Autodesk Fusion 360 part; units mm, degrees
(part 2 of 3)
sketch "Tip bolt 102 -10 sketch" plane through (0, 0, -0.05) normal (0, 0, 1) x (1, 0, 0) in component "01C Wing tip - load adapter"
  circle A0 centre (102, -10) radius 1.7
  dimension "d328" = 3.4
  measures "d328" diameter of A0
extrude "Tip bolt 102 -10" cut sketch "Tip bolt 102 -10 sketch" along normal blind 9.1 bodies 3 in component "01C Wing tip - load adapter"
ref_plane "WorkPlane15" through (0, 0, -0.05) normal (0, 0, 1) x (1, 0, 0) in component "01C Wing tip - load adapter"
sketch "Tip bolt 102 10 sketch" plane through (0, 0, -0.05) normal (0, 0, 1) x (1, 0, 0) in component "01C Wing tip - load adapter"
  circle A0 centre (102, 10) radius 1.7
  dimension "d333" = 3.4
  measures "d333" diameter of A0
extrude "Tip bolt 102 10" cut sketch "Tip bolt 102 10 sketch" along normal blind 9.1 bodies 3 in component "01C Wing tip - load adapter"
ref_plane "WorkPlane16" through (0, 0, -0.05) normal (0, 0, 1) x (1, 0, 0) in component "01C Wing tip - load adapter"
sketch "Tip bolt 110 -10 sketch" plane through (0, 0, -0.05) normal (0, 0, 1) x (1, 0, 0) in component "01C Wing tip - load adapter"
  circle A0 centre (110, -10) radius 1.7
  dimension "d338" = 3.4
  measures "d338" diameter of A0
extrude "Tip bolt 110 -10" cut sketch "Tip bolt 110 -10 sketch" along normal blind 9.1 bodies 3 in component "01C Wing tip - load adapter"
ref_plane "WorkPlane17" through (0, 0, -0.05) normal (0, 0, 1) x (1, 0, 0) in component "01C Wing tip - load adapter"
sketch "Tip bolt 110 10 sketch" plane through (0, 0, -0.05) normal (0, 0, 1) x (1, 0, 0) in component "01C Wing tip - load adapter"
  circle A0 centre (110, 10) radius 1.7
  dimension "d343" = 3.4
  measures "d343" diameter of A0
extrude "Tip bolt 110 10" cut sketch "Tip bolt 110 10 sketch" along normal blind 9.1 bodies 3 in component "01C Wing tip - load adapter"
ref_plane "WorkPlane18" through (-0.05, 0, 0) normal (1, 0, 0) x (0, 1, 0) in component "01C Wing tip - load adapter"
sketch "front diamond bamboo passage sketch (3)" plane through (-0.05, 0, 0) normal (1, 0, 0) x (0, 0, -1) in component "01C Wing tip - load adapter"
  line L0 (-4.5, -21.182) -> (-1.318, -18)
  line L1 (-1.318, -18) -> (-4.5, -14.818)
  line L2 (-4.5, -14.818) -> (-7.682, -18)
  line L3 (-7.682, -18) -> (-4.5, -21.182)
  line L4 (-4.5, -21.182) -> (-4.5, -14.818) construction
  line L5 (-1.318, -18) -> (-7.682, -18) construction
  point P0 (-4.5, -18)
  dimension "d348" = 6.364
  constraint vertical L4
  constraint horizontal L5
  constraint midpoint L4 P0
  constraint midpoint L5 P0
  constraint equal L4 L5
  measures "d348" distance of L0.end L2.end
extrude "front diamond bamboo passage''" cut sketch "front diamond bamboo passage sketch (3)" along normal blind 112.05 bodies 3 in component "01C Wing tip - load adapter"
ref_plane "WorkPlane19" through (-0.05, 0, 0) normal (1, 0, 0) x (0, 1, 0) in component "01C Wing tip - load adapter"
sketch "rear diamond bamboo passage sketch (3)" plane through (-0.05, 0, 0) normal (1, 0, 0) x (0, 0, -1) in component "01C Wing tip - load adapter"
  line L0 (-4.5, 14.818) -> (-1.318, 18)
  line L1 (-1.318, 18) -> (-4.5, 21.182)
  line L2 (-4.5, 21.182) -> (-7.682, 18)
  line L3 (-7.682, 18) -> (-4.5, 14.818)
  line L4 (-4.5, 14.818) -> (-4.5, 21.182) construction
  line L5 (-1.318, 18) -> (-7.682, 18) construction
  point P0 (-4.5, 18)
  dimension "d353" = 6.364
  constraint vertical L4
  constraint horizontal L5
  constraint midpoint L4 P0
  constraint midpoint L5 P0
  constraint equal L4 L5
  measures "d353" distance of L0.end L2.end
extrude "rear diamond bamboo passage''" cut sketch "rear diamond bamboo passage sketch (3)" along normal blind 112.05 bodies 3 in component "01C Wing tip - load adapter"
sketch "Flat joint plate sketch" plane through (0, 0, 0) normal (0, 0, 1) x (1, 0, 0) in component "07 Joint sandwich plate - print FOUR"
  line L0 (0, -10) -> (24.2, -10)
  line L1 (24.2, -10) -> (24.2, 10)
  line L2 (24.2, 10) -> (0, 10)
  line L3 (0, 10) -> (0, -10)
extrude "Flat joint plate" add sketch "Flat joint plate sketch" along normal blind 2 separate body makes body 4 in component "07 Joint sandwich plate - print FOUR"
ref_plane "WorkPlane1" through (0, 0, -0.05) normal (0, 0, 1) x (1, 0, 0) in component "07 Joint sandwich plate - print FOUR"
sketch "Seam bolt 6 sketch" plane through (0, 0, -0.05) normal (0, 0, 1) x (1, 0, 0) in component "07 Joint sandwich plate - print FOUR"
  circle A0 centre (6, 0) radius 1.7
  dimension "d360" = 3.4
  measures "d360" diameter of A0
extrude "Seam bolt 6" cut sketch "Seam bolt 6 sketch" along normal blind 2.1 bodies 4 in component "07 Joint sandwich plate - print FOUR"
ref_plane "WorkPlane2" through (0, 0, -0.05) normal (0, 0, 1) x (1, 0, 0) in component "07 Joint sandwich plate - print FOUR"
sketch "Seam bolt 18.2 sketch" plane through (0, 0, -0.05) normal (0, 0, 1) x (1, 0, 0) in component "07 Joint sandwich plate - print FOUR"
  circle A0 centre (18.2, 0) radius 1.7
  dimension "d365" = 3.4
  measures "d365" diameter of A0
extrude "Seam bolt 18.2" cut sketch "Seam bolt 18.2 sketch" along normal blind 2.1 bodies 4 in component "07 Joint sandwich plate - print FOUR"
sketch "Bench mounting plate sketch" plane through (0, 0, 0) normal (0, 0, 1) x (1, 0, 0) in component "02 Root base - bench clamp"
  line L0 (-82, -50) -> (28, -50)
  line L1 (28, -50) -> (28, 50)
  line L2 (28, 50) -> (-82, 50)
  line L3 (-82, 50) -> (-82, -50)
extrude "Bench mounting plate" add sketch "Bench mounting plate sketch" along normal blind 8 separate body makes body 5 in component "02 Root base - bench clamp"
ref_plane "WorkPlane1" through (0, 0, 8) normal (0, 0, 1) x (1, 0, 0) in component "02 Root base - bench clamp"
sketch "Lower root jaw sketch" plane through (0, 0, 8) normal (0, 0, 1) x (1, 0, 0) in component "02 Root base - bench clamp"
  line L0 (-4, -49) -> (26, -49)
  line L1 (26, -49) -> (26, 49)
  line L2 (26, 49) -> (-4, 49)
  line L3 (-4, 49) -> (-4, -49)
extrude "Lower root jaw" add sketch "Lower root jaw sketch" along normal blind 8 bodies 5 in component "02 Root base - bench clamp"
ref_plane "WorkPlane2" through (0, 0, 15.95) normal (0, 0, 1) x (1, 0, 0) in component "02 Root base - bench clamp"
sketch "Root pin -8 sketch" plane through (0, 0, 15.95) normal (0, 0, 1) x (1, 0, 0) in component "02 Root base - bench clamp"
  circle A0 centre (8, -8) radius 1.5
extrude "Root pin -8" add sketch "Root pin -8 sketch" along normal blind 2.05 bodies 5 in component "02 Root base - bench clamp"
ref_plane "WorkPlane3" through (0, 0, 15.95) normal (0, 0, 1) x (1, 0, 0) in component "02 Root base - bench clamp"
sketch "Root pin 8 sketch" plane through (0, 0, 15.95) normal (0, 0, 1) x (1, 0, 0) in component "02 Root base - bench clamp"
  circle A0 centre (8, 8) radius 1.5
extrude "Root pin 8" add sketch "Root pin 8 sketch" along normal blind 2.05 bodies 5 in component "02 Root base - bench clamp"
ref_plane "WorkPlane4" through (0, 0, -0.05) normal (0, 0, 1) x (1, 0, 0) in component "02 Root base - bench clamp"
sketch "Jaw bolt 3 -43 sketch" plane through (0, 0, -0.05) normal (0, 0, 1) x (1, 0, 0) in component "02 Root base - bench clamp"
  circle A0 centre (3, -43) radius 2.2
  dimension "d384" = 4.4
  measures "d384" diameter of A0
extrude "Jaw bolt 3 -43" cut sketch "Jaw bolt 3 -43 sketch" along normal blind 16.1 bodies 5 in component "02 Root base - bench clamp"
ref_plane "WorkPlane5" through (0, 0, -0.05) normal (0, 0, 1) x (1, 0, 0) in component "02 Root base - bench clamp"
sketch "Nut pocket 3 -43 sketch" plane through (0, 0, -0.05) normal (0, 0, 1) x (1, 0, 0) in component "02 Root base - bench clamp"
  line L0 (6.55, -40.9504) -> (3, -38.9008)
  line L1 (3, -38.9008) -> (-0.55, -40.9504)
  line L2 (-0.55, -40.9504) -> (-0.55, -45.0496)
  line L3 (-0.55, -45.0496) -> (3, -47.0992)
  line L4 (3, -47.0992) -> (6.55, -45.0496)
  line L5 (6.55, -45.0496) -> (6.55, -40.9504)
extrude "Nut pocket 3 -43" cut sketch "Nut pocket 3 -43 sketch" along normal blind 3.35 bodies 5 in component "02 Root base - bench clamp"
ref_plane "WorkPlane6" through (0, 0, -0.05) normal (0, 0, 1) x (1, 0, 0) in component "02 Root base - bench clamp"
sketch "Jaw bolt 3 43 sketch" plane through (0, 0, -0.05) normal (0, 0, 1) x (1, 0, 0) in component "02 Root base - bench clamp"
  circle A0 centre (3, 43) radius 2.2
  dimension "d393" = 4.4
  measures "d393" diameter of A0
extrude "Jaw bolt 3 43" cut sketch "Jaw bolt 3 43 sketch" along normal blind 16.1 bodies 5 in component "02 Root base - bench clamp"
ref_plane "WorkPlane7" through (0, 0, -0.05) normal (0, 0, 1) x (1, 0, 0) in component "02 Root base - bench clamp"
sketch "Nut pocket 3 43 sketch" plane through (0, 0, -0.05) normal (0, 0, 1) x (1, 0, 0) in component "02 Root base - bench clamp"
  line L0 (6.55, 45.0496) -> (3, 47.0992)
  line L1 (3, 47.0992) -> (-0.55, 45.0496)
  line L2 (-0.55, 45.0496) -> (-0.55, 40.9504)
  line L3 (-0.55, 40.9504) -> (3, 38.9008)
  line L4 (3, 38.9008) -> (6.55, 40.9504)
  line L5 (6.55, 40.9504) -> (6.55, 45.0496)
extrude "Nut pocket 3 43" cut sketch "Nut pocket 3 43 sketch" along normal blind 3.35 bodies 5 in component "02 Root base - bench clamp"
ref_plane "WorkPlane8" through (0, 0, -0.05) normal (0, 0, 1) x (1, 0, 0) in component "02 Root base - bench clamp"
sketch "Jaw bolt 20 -43 sketch" plane through (0, 0, -0.05) normal (0, 0, 1) x (1, 0, 0) in component "02 Root base - bench clamp"
  circle A0 centre (20, -43) radius 2.2
  dimension "d402" = 4.4
  measures "d402" diameter of A0
extrude "Jaw bolt 20 -43" cut sketch "Jaw bolt 20 -43 sketch" along normal blind 16.1 bodies 5 in component "02 Root base - bench clamp"
ref_plane "WorkPlane9" through (0, 0, -0.05) normal (0, 0, 1) x (1, 0, 0) in component "02 Root base - bench clamp"
sketch "Nut pocket 20 -43 sketch" plane through (0, 0, -0.05) normal (0, 0, 1) x (1, 0, 0) in component "02 Root base - bench clamp"
  line L0 (23.55, -40.9504) -> (20, -38.9008)
  line L1 (20, -38.9008) -> (16.45, -40.9504)
  line L2 (16.45, -40.9504) -> (16.45, -45.0496)
  line L3 (16.45, -45.0496) -> (20, -47.0992)
  line L4 (20, -47.0992) -> (23.55, -45.0496)
  line L5 (23.55, -45.0496) -> (23.55, -40.9504)
extrude "Nut pocket 20 -43" cut sketch "Nut pocket 20 -43 sketch" along normal blind 3.35 bodies 5 in component "02 Root base - bench clamp"
ref_plane "WorkPlane10" through (0, 0, -0.05) normal (0, 0, 1) x (1, 0, 0) in component "02 Root base - bench clamp"
sketch "Jaw bolt 20 43 sketch" plane through (0, 0, -0.05) normal (0, 0, 1) x (1, 0, 0) in component "02 Root base - bench clamp"
  circle A0 centre (20, 43) radius 2.2
  dimension "d411" = 4.4
  measures "d411" diameter of A0
extrude "Jaw bolt 20 43" cut sketch "Jaw bolt 20 43 sketch" along normal blind 16.1 bodies 5 in component "02 Root base - bench clamp"
ref_plane "WorkPlane11" through (0, 0, -0.05) normal (0, 0, 1) x (1, 0, 0) in component "02 Root base - bench clamp"
sketch "Nut pocket 20 43 sketch" plane through (0, 0, -0.05) normal (0, 0, 1) x (1, 0, 0) in component "02 Root base - bench clamp"
  line L0 (23.55, 45.0496) -> (20, 47.0992)
  line L1 (20, 47.0992) -> (16.45, 45.0496)
  line L2 (16.45, 45.0496) -> (16.45, 40.9504)
  line L3 (16.45, 40.9504) -> (20, 38.9008)
  line L4 (20, 38.9008) -> (23.55, 40.9504)
  line L5 (23.55, 40.9504) -> (23.55, 45.0496)
extrude "Nut pocket 20 43" cut sketch "Nut pocket 20 43 sketch" along normal blind 3.35 bodies 5 in component "02 Root base - bench clamp"
ref_plane "WorkPlane12" through (0, 0, -0.05) normal (0, 0, 1) x (1, 0, 0) in component "02 Root base - bench clamp"
sketch "Bench slot -32 sketch" plane through (0, 0, -0.05) normal (0, 0, 1) x (1, 0, 0) in component "02 Root base - bench clamp"
  arc A0 (-68, -28.7) -> (-68, -35.3) centre (-68, -32) ccw
  line L0 (-68, -28.7) -> (-48, -28.7)
  arc A1 (-48, -35.3) -> (-48, -28.7) centre (-48, -32) ccw
  line L1 (-48, -35.3) -> (-68, -35.3)
extrude "Bench slot -32" cut sketch "Bench slot -32 sketch" along normal blind 8.1 bodies 5 in component "02 Root base - bench clamp"
ref_plane "WorkPlane13" through (0, 0, -0.05) normal (0, 0, 1) x (1, 0, 0) in component "02 Root base - bench clamp"
sketch "Bench slot 32 sketch" plane through (0, 0, -0.05) normal (0, 0, 1) x (1, 0, 0) in component "02 Root base - bench clamp"
  arc A0 (-68, 35.3) -> (-68, 28.7) centre (-68, 32) ccw
  line L0 (-68, 35.3) -> (-48, 35.3)
  arc A1 (-48, 28.7) -> (-48, 35.3) centre (-48, 32) ccw
  line L1 (-48, 28.7) -> (-68, 28.7)
extrude "Bench slot 32" cut sketch "Bench slot 32 sketch" along normal blind 8.1 bodies 5 in component "02 Root base - bench clamp"
sketch "Upper root jaw sketch" plane through (0, 0, 0) normal (0, 0, 1) x (1, 0, 0) in component "03 Root cap"
  line L0 (-4, -49) -> (26, -49)
  line L1 (26, -49) -> (26, 49)
  line L2 (26, 49) -> (-4, 49)
  line L3 (-4, 49) -> (-4, -49)
extrude "Upper root jaw" add sketch "Upper root jaw sketch" along normal blind 8 separate body makes body 6 in component "03 Root cap"
ref_plane "WorkPlane1" through (0, 0, -0.05) normal (0, 0, 1) x (1, 0, 0) in component "03 Root cap"
sketch "Cap bolt 3 -43 sketch" plane through (0, 0, -0.05) normal (0, 0, 1) x (1, 0, 0) in component "03 Root cap"
  circle A0 centre (3, -43) radius 2.2
  dimension "d430" = 4.4
  measures "d430" diameter of A0
extrude "Cap bolt 3 -43" cut sketch "Cap bolt 3 -43 sketch" along normal blind 8.1 bodies 6 in component "03 Root cap"
ref_plane "WorkPlane2" through (0, 0, -0.05) normal (0, 0, 1) x (1, 0, 0) in component "03 Root cap"
sketch "Cap bolt 3 43 sketch" plane through (0, 0, -0.05) normal (0, 0, 1) x (1, 0, 0) in component "03 Root cap"
  circle A0 centre (3, 43) radius 2.2
  dimension "d435" = 4.4
  measures "d435" diameter of A0
extrude "Cap bolt 3 43" cut sketch "Cap bolt 3 43 sketch" along normal blind 8.1 bodies 6 in component "03 Root cap"
ref_plane "WorkPlane3" through (0, 0, -0.05) normal (0, 0, 1) x (1, 0, 0) in component "03 Root cap"
sketch "Cap bolt 20 -43 sketch" plane through (0, 0, -0.05) normal (0, 0, 1) x (1, 0, 0) in component "03 Root cap"
  circle A0 centre (20, -43) radius 2.2
  dimension "d440" = 4.4
  measures "d440" diameter of A0
extrude "Cap bolt 20 -43" cut sketch "Cap bolt 20 -43 sketch" along normal blind 8.1 bodies 6 in component "03 Root cap"
ref_plane "WorkPlane4" through (0, 0, -0.05) normal (0, 0, 1) x (1, 0, 0) in component "03 Root cap"
sketch "Cap bolt 20 43 sketch" plane through (0, 0, -0.05) normal (0, 0, 1) x (1, 0, 0) in component "03 Root cap"
  circle A0 centre (20, 43) radius 2.2
  dimension "d445" = 4.4
  measures "d445" diameter of A0
extrude "Cap bolt 20 43" cut sketch "Cap bolt 20 43 sketch" along normal blind 8.1 bodies 6 in component "03 Root cap"
sketch "Adapter plate sketch" plane through (0, 0, 0) normal (0, 0, 1) x (1, 0, 0) in component "04 Tip adapter - adjustable glue mount rails"
  line L0 (0, -19) -> (90, -19)
  line L1 (90, -19) -> (90, 19)
  line L2 (90, 19) -> (0, 19)
  line L3 (0, 19) -> (0, -19)
extrude "Adapter plate" add sketch "Adapter plate sketch" along normal blind 6 separate body makes body 7 in component "04 Tip adapter - adjustable glue mount rails"
ref_plane "WorkPlane1" through (0, 0, -0.05) normal (0, 0, 1) x (1, 0, 0) in component "04 Tip adapter - adjustable glue mount rails"
sketch "Wing adapter bolt 4 -10 sketch" plane through (0, 0, -0.05) normal (0, 0, 1) x (1, 0, 0) in component "04 Tip adapter - adjustable glue mount rails"
  circle A0 centre (4, -10) radius 1.7
  dimension "d452" = 3.4
  measures "d452" diameter of A0
extrude "Wing adapter bolt 4 -10" cut sketch "Wing adapter bolt 4 -10 sketch" along normal blind 6.1 bodies 7 in component "04 Tip adapter - adjustable glue mount rails"
ref_plane "WorkPlane2" through (0, 0, -0.05) normal (0, 0, 1) x (1, 0, 0) in component "04 Tip adapter - adjustable glue mount rails"
sketch "Wing adapter bolt 4 10 sketch" plane through (0, 0, -0.05) normal (0, 0, 1) x (1, 0, 0) in component "04 Tip adapter - adjustable glue mount rails"
  circle A0 centre (4, 10) radius 1.7
  dimension "d457" = 3.4
  measures "d457" diameter of A0
extrude "Wing adapter bolt 4 10" cut sketch "Wing adapter bolt 4 10 sketch" along normal blind 6.1 bodies 7 in component "04 Tip adapter - adjustable glue mount rails"
ref_plane "WorkPlane3" through (0, 0, -0.05) normal (0, 0, 1) x (1, 0, 0) in component "04 Tip adapter - adjustable glue mount rails"
sketch "Wing adapter bolt 12 -10 sketch" plane through (0, 0, -0.05) normal (0, 0, 1) x (1, 0, 0) in component "04 Tip adapter - adjustable glue mount rails"
  circle A0 centre (12, -10) radius 1.7
  dimension "d462" = 3.4
  measures "d462" diameter of A0
extrude "Wing adapter bolt 12 -10" cut sketch "Wing adapter bolt 12 -10 sketch" along normal blind 6.1 bodies 7 in component "04 Tip adapter - adjustable glue mount rails"
ref_plane "WorkPlane4" through (0, 0, -0.05) normal (0, 0, 1) x (1, 0, 0) in component "04 Tip adapter - adjustable glue mount rails"
sketch "Wing adapter bolt 12 10 sketch" plane through (0, 0, -0.05) normal (0, 0, 1) x (1, 0, 0) in component "04 Tip adapter - adjustable glue mount rails"
  circle A0 centre (12, 10) radius 1.7
  dimension "d467" = 3.4
  measures "d467" diameter of A0
extrude "Wing adapter bolt 12 10" cut sketch "Wing adapter bolt 12 10 sketch" along normal blind 6.1 bodies 7 in component "04 Tip adapter - adjustable glue mount rails"
ref_plane "WorkPlane5" through (0, 0, -0.05) normal (0, 0, 1) x (1, 0, 0) in component "04 Tip adapter - adjustable glue mount rails"
sketch "Fixed mount sliding rail -11 sketch" plane through (0, 0, -0.05) normal (0, 0, 1) x (1, 0, 0) in component "04 Tip adapter - adjustable glue mount rails"
  arc A0 (24, -9.3) -> (24, -12.7) centre (24, -11) ccw
  line L0 (24, -9.3) -> (76, -9.3)
  arc A1 (76, -12.7) -> (76, -9.3) centre (76, -11) ccw
  line L1 (76, -12.7) -> (24, -12.7)
extrude "Fixed mount sliding rail -11" cut sketch "Fixed mount sliding rail -11 sketch" along normal blind 6.1 bodies 7 in component "04 Tip adapter - adjustable glue mount rails"
ref_plane "WorkPlane6" through (0, 0, -0.05) normal (0, 0, 1) x (1, 0, 0) in component "04 Tip adapter - adjustable glue mount rails"
sketch "Fixed mount sliding rail 11 sketch" plane through (0, 0, -0.05) normal (0, 0, 1) x (1, 0, 0) in component "04 Tip adapter - adjustable glue mount rails"
  arc A0 (24, 12.7) -> (24, 9.3) centre (24, 11) ccw
  line L0 (24, 12.7) -> (76, 12.7)
  arc A1 (76, 9.3) -> (76, 12.7) centre (76, 11) ccw
  line L1 (76, 9.3) -> (24, 9.3)
extrude "Fixed mount sliding rail 11" cut sketch "Fixed mount sliding rail 11 sketch" along normal blind 6.1 bodies 7 in component "04 Tip adapter - adjustable glue mount rails"
sketch "Glue carrier body sketch" plane through (0, 0, 0) normal (0, 0, 1) x (1, 0, 0) in component "05 Fixed end glue pedestal"
  line L0 (-13, -17) -> (13, -17)
  line L1 (13, -17) -> (13, 17)
  line L2 (13, 17) -> (-13, 17)
  line L3 (-13, 17) -> (-13, -17)
extrude "Glue carrier body" add sketch "Glue carrier body sketch" along normal blind 20 separate body makes body 8 in component "05 Fixed end glue pedestal"
ref_plane "WorkPlane1" through (0, 0, 19.95) normal (0, 0, 1) x (1, 0, 0) in component "05 Fixed end glue pedestal"
sketch "END ONLY 10x24 glue landing sketch" plane through (0, 0, 19.95) normal (0, 0, 1) x (1, 0, 0) in component "05 Fixed end glue pedestal"
  line L0 (-5, -12) -> (5, -12)
  line L1 (5, -12) -> (5, 12)
  line L2 (5, 12) -> (-5, 12)
  line L3 (-5, 12) -> (-5, -12)
extrude "END ONLY 10x24 glue landing" add sketch "END ONLY 10x24 glue landing sketch" along normal blind 1.25 bodies 8 in component "05 Fixed end glue pedestal"
ref_plane "WorkPlane2" through (0, 0, 20.7) normal (0, 0, 1) x (1, 0, 0) in component "05 Fixed end glue pedestal"
sketch "Shallow glue key groove -3 sketch" plane through (0, 0, 20.7) normal (0, 0, 1) x (1, 0, 0) in component "05 Fixed end glue pedestal"
  line L0 (-3.4, -10) -> (-2.6, -10)
  line L1 (-2.6, -10) -> (-2.6, 10)
  line L2 (-2.6, 10) -> (-3.4, 10)
  line L3 (-3.4, 10) -> (-3.4, -10)
extrude "Shallow glue key groove -3" cut sketch "Shallow glue key groove -3 sketch" along normal blind 0.6 bodies 8 in component "05 Fixed end glue pedestal"
ref_plane "WorkPlane3" through (0, 0, 20.7) normal (0, 0, 1) x (1, 0, 0) in component "05 Fixed end glue pedestal"
sketch "Shallow glue key groove 0 sketch" plane through (0, 0, 20.7) normal (0, 0, 1) x (1, 0, 0) in component "05 Fixed end glue pedestal"
  line L0 (-0.4, -10) -> (0.4, -10)
  line L1 (0.4, -10) -> (0.4, 10)
  line L2 (0.4, 10) -> (-0.4, 10)
  line L3 (-0.4, 10) -> (-0.4, -10)
extrude "Shallow glue key groove 0" cut sketch "Shallow glue key groove 0 sketch" along normal blind 0.6 bodies 8 in component "05 Fixed end glue pedestal"
ref_plane "WorkPlane4" through (0, 0, 20.7) normal (0, 0, 1) x (1, 0, 0) in component "05 Fixed end glue pedestal"
sketch "Shallow glue key groove 3 sketch" plane through (0, 0, 20.7) normal (0, 0, 1) x (1, 0, 0) in component "05 Fixed end glue pedestal"
  line L0 (2.6, -10) -> (3.4, -10)
  line L1 (3.4, -10) -> (3.4, 10)
  line L2 (3.4, 10) -> (2.6, 10)
  line L3 (2.6, 10) -> (2.6, -10)
extrude "Shallow glue key groove 3" cut sketch "Shallow glue key groove 3 sketch" along normal blind 0.6 bodies 8 in component "05 Fixed end glue pedestal"
ref_plane "WorkPlane5" through (0, 0, -0.05) normal (0, 0, 1) x (1, 0, 0) in component "05 Fixed end glue pedestal"
sketch "Optional tie return slot -13.5 sketch" plane through (0, 0, -0.05) normal (0, 0, 1) x (1, 0, 0) in component "05 Fixed end glue pedestal"
  arc A0 (-1, -12.3) -> (-1, -14.7) centre (-1, -13.5) ccw
  line L0 (-1, -12.3) -> (1, -12.3)
  arc A1 (1, -14.7) -> (1, -12.3) centre (1, -13.5) ccw
  line L1 (1, -14.7) -> (-1, -14.7)
extrude "Optional tie return slot -13.5" cut sketch "Optional tie return slot -13.5 sketch" along normal blind 20.1 bodies 8 in component "05 Fixed end glue pedestal"
ref_plane "WorkPlane6" through (0, 0, -0.05) normal (0, 0, 1) x (1, 0, 0) in component "05 Fixed end glue pedestal"
sketch "Optional tie return slot 13.5 sketch" plane through (0, 0, -0.05) normal (0, 0, 1) x (1, 0, 0) in component "05 Fixed end glue pedestal"
  arc A0 (-1, 14.7) -> (-1, 12.3) centre (-1, 13.5) ccw
  line L0 (-1, 14.7) -> (1, 14.7)
  arc A1 (1, 12.3) -> (1, 14.7) centre (1, 13.5) ccw
  line L1 (1, 12.3) -> (-1, 12.3)
extrude "Optional tie return slot 13.5" cut sketch "Optional tie return slot 13.5 sketch" along normal blind 20.1 bodies 8 in component "05 Fixed end glue pedestal"
ref_plane "WorkPlane7" through (0, 0, -0.05) normal (0, 0, 1) x (1, 0, 0) in component "05 Fixed end glue pedestal"
sketch "Pedestal rail bolt -9 -11 sketch" plane through (0, 0, -0.05) normal (0, 0, 1) x (1, 0, 0) in component "05 Fixed end glue pedestal"
  circle A0 centre (-9, -11) radius 1.7
  dimension "d506" = 3.4
  measures "d506" diameter of A0
extrude "Pedestal rail bolt -9 -11" cut sketch "Pedestal rail bolt -9 -11 sketch" along normal blind 20.1 bodies 8 in component "05 Fixed end glue pedestal"
ref_plane "WorkPlane8" through (0, 0, -0.05) normal (0, 0, 1) x (1, 0, 0) in component "05 Fixed end glue pedestal"
sketch "Pedestal rail bolt -9 11 sketch" plane through (0, 0, -0.05) normal (0, 0, 1) x (1, 0, 0) in component "05 Fixed end glue pedestal"
  circle A0 centre (-9, 11) radius 1.7
  dimension "d511" = 3.4
  measures "d511" diameter of A0
extrude "Pedestal rail bolt -9 11" cut sketch "Pedestal rail bolt -9 11 sketch" along normal blind 20.1 bodies 8 in component "05 Fixed end glue pedestal"
ref_plane "WorkPlane9" through (0, 0, -0.05) normal (0, 0, 1) x (1, 0, 0) in component "05 Fixed end glue pedestal"
sketch "Pedestal rail bolt 9 -11 sketch" plane through (0, 0, -0.05) normal (0, 0, 1) x (1, 0, 0) in component "05 Fixed end glue pedestal"
  circle A0 centre (9, -11) radius 1.7
  dimension "d516" = 3.4
  measures "d516" diameter of A0
extrude "Pedestal rail bolt 9 -11" cut sketch "Pedestal rail bolt 9 -11 sketch" along normal blind 20.1 bodies 8 in component "05 Fixed end glue pedestal"
ref_plane "WorkPlane10" through (0, 0, -0.05) normal (0, 0, 1) x (1, 0, 0) in component "05 Fixed end glue pedestal"
sketch "Pedestal rail bolt 9 11 sketch" plane through (0, 0, -0.05) normal (0, 0, 1) x (1, 0, 0) in component "05 Fixed end glue pedestal"
  circle A0 centre (9, 11) radius 1.7
  dimension "d521" = 3.4
  measures "d521" diameter of A0
extrude "Pedestal rail bolt 9 11" cut sketch "Pedestal rail bolt 9 11 sketch" along normal blind 20.1 bodies 8 in component "05 Fixed end glue pedestal"
sketch "Glue carrier body sketch (2)" plane through (0, 0, 0) normal (0, 0, 1) x (1, 0, 0) in component "06 Free end glue hanger"
  line L0 (-13, -17) -> (13, -17)
  line L1 (13, -17) -> (13, 17)
  line L2 (13, 17) -> (-13, 17)
  line L3 (-13, 17) -> (-13, -17)
extrude "Glue carrier body'" add sketch "Glue carrier body sketch (2)" along normal blind 10 separate body makes body 9 in component "06 Free end glue hanger"
ref_plane "WorkPlane1" through (0, 0, 9.95) normal (0, 0, 1) x (1, 0, 0) in component "06 Free end glue hanger"
sketch "END ONLY 10x24 glue landing sketch (2)" plane through (0, 0, 9.95) normal (0, 0, 1) x (1, 0, 0) in component "06 Free end glue hanger"
  line L0 (-5, -12) -> (5, -12)
  line L1 (5, -12) -> (5, 12)
  line L2 (5, 12) -> (-5, 12)
  line L3 (-5, 12) -> (-5, -12)
extrude "END ONLY 10x24 glue landing'" add sketch "END ONLY 10x24 glue landing sketch (2)" along normal blind 1.25 bodies 9 in component "06 Free end glue hanger"
ref_plane "WorkPlane2" through (0, 0, 10.7) normal (0, 0, 1) x (1, 0, 0) in component "06 Free end glue hanger"
sketch "Shallow glue key groove -3 sketch (2)" plane through (0, 0, 10.7) normal (0, 0, 1) x (1, 0, 0) in component "06 Free end glue hanger"
  line L0 (-3.4, -10) -> (-2.6, -10)
  line L1 (-2.6, -10) -> (-2.6, 10)
  line L2 (-2.6, 10) -> (-3.4, 10)
  line L3 (-3.4, 10) -> (-3.4, -10)
extrude "Shallow glue key groove -3'" cut sketch "Shallow glue key groove -3 sketch (2)" along normal blind 0.6 bodies 9 in component "06 Free end glue hanger"
ref_plane "WorkPlane3" through (0, 0, 10.7) normal (0, 0, 1) x (1, 0, 0) in component "06 Free end glue hanger"
sketch "Shallow glue key groove 0 sketch (2)" plane through (0, 0, 10.7) normal (0, 0, 1) x (1, 0, 0) in component "06 Free end glue hanger"
  line L0 (-0.4, -10) -> (0.4, -10)
  line L1 (0.4, -10) -> (0.4, 10)
  line L2 (0.4, 10) -> (-0.4, 10)
  line L3 (-0.4, 10) -> (-0.4, -10)
extrude "Shallow glue key groove 0'" cut sketch "Shallow glue key groove 0 sketch (2)" along normal blind 0.6 bodies 9 in component "06 Free end glue hanger"
ref_plane "WorkPlane4" through (0, 0, 10.7) normal (0, 0, 1) x (1, 0, 0) in component "06 Free end glue hanger"
sketch "Shallow glue key groove 3 sketch (2)" plane through (0, 0, 10.7) normal (0, 0, 1) x (1, 0, 0) in component "06 Free end glue hanger"
  line L0 (2.6, -10) -> (3.4, -10)
  line L1 (3.4, -10) -> (3.4, 10)
  line L2 (3.4, 10) -> (2.6, 10)
  line L3 (2.6, 10) -> (2.6, -10)
extrude "Shallow glue key groove 3'" cut sketch "Shallow glue key groove 3 sketch (2)" along normal blind 0.6 bodies 9 in component "06 Free end glue hanger"
ref_plane "WorkPlane5" through (0, 0, -0.05) normal (0, 0, 1) x (1, 0, 0) in component "06 Free end glue hanger"
sketch "Optional tie return slot -13.5 sketch (2)" plane through (0, 0, -0.05) normal (0, 0, 1) x (1, 0, 0) in component "06 Free end glue hanger"
  arc A0 (-1, -12.3) -> (-1, -14.7) centre (-1, -13.5) ccw
  line L0 (-1, -12.3) -> (1, -12.3)
  arc A1 (1, -14.7) -> (1, -12.3) centre (1, -13.5) ccw
  line L1 (1, -14.7) -> (-1, -14.7)
extrude "Optional tie return slot -13.5'" cut sketch "Optional tie return slot -13.5 sketch (2)" along normal blind 10.1 bodies 9 in component "06 Free end glue hanger"
ref_plane "WorkPlane6" through (0, 0, -0.05) normal (0, 0, 1) x (1, 0, 0) in component "06 Free end glue hanger"
sketch "Optional tie return slot 13.5 sketch (2)" plane through (0, 0, -0.05) normal (0, 0, 1) x (1, 0, 0) in component "06 Free end glue hanger"
  arc A0 (-1, 14.7) -> (-1, 12.3) centre (-1, 13.5) ccw
  line L0 (-1, 14.7) -> (1, 14.7)
  arc A1 (1, 12.3) -> (1, 14.7) centre (1, 13.5) ccw
  line L1 (1, 12.3) -> (-1, 12.3)
extrude "Optional tie return slot 13.5'" cut sketch "Optional tie return slot 13.5 sketch (2)" along normal blind 10.1 bodies 9 in component "06 Free end glue hanger"
sketch "Transverse cord hole sketch" plane through (0, 0, 0) normal (0, 1, 0) x (1, 0, 0) in component "06 Free end glue hanger"
  circle A0 centre (0, -5) radius 1.75
extrude "Transverse cord hole" cut sketch "Transverse cord hole sketch" along normal mid plane 34.1 bodies 9 in component "06 Free end glue hanger"
sketch "Fit block sketch" plane through (0, 0, 0) normal (0, 0, 1) x (1, 0, 0) in component "07 Spar fit coupon - 4.1 4.3 4.4 4.5 4.7"
  line L0 (0, 0) -> (24, 0)
  line L1 (24, 0) -> (24, 60)
  line L2 (24, 60) -> (0, 60)
  line L3 (0, 60) -> (0, 0)
extrude "Fit block" add sketch "Fit block sketch" along normal blind 10 separate body makes body 10 in component "07 Spar fit coupon - 4.1 4.3 4.4 4.5 4.7"
ref_plane "WorkPlane1" through (-0.05, 0, 0) normal (1, 0, 0) x (0, 1, 0) in component "07 Spar fit coupon - 4.1 4.3 4.4 4.5 4.7"
sketch "Diamond 4.1 mm flat-width fit bore sketch" plane through (-0.05, 0, 0) normal (1, 0, 0) x (0, 0, -1) in component "07 Spar fit coupon - 4.1 4.3 4.4 4.5 4.7"
  line L0 (-4.5, 3.1009) -> (-1.6009, 6)
  line L1 (-1.6009, 6) -> (-4.5, 8.8991)
  line L2 (-4.5, 8.8991) -> (-7.3991, 6)
  line L3 (-7.3991, 6) -> (-4.5, 3.1009)
extrude "Diamond 4.1 mm flat-width fit bore" cut sketch "Diamond 4.1 mm flat-width fit bore sketch" along normal blind 24.1 bodies 10 in component "07 Spar fit coupon - 4.1 4.3 4.4 4.5 4.7"
ref_plane "WorkPlane2" through (0, 0, 9.4) normal (0, 0, 1) x (1, 0, 0) in component "07 Spar fit coupon - 4.1 4.3 4.4 4.5 4.7"
sketch "Label 4.1 digit 0 f sketch" plane through (0, 0, 9.4) normal (0, 0, 1) x (1, 0, 0) in component "07 Spar fit coupon - 4.1 4.3 4.4 4.5 4.7"
  line L0 (8, 6.15) -> (8.3, 6.15)
  line L1 (8.3, 6.15) -> (8.3, 7.05)
  line L2 (8.3, 7.05) -> (8, 7.05)
  line L3 (8, 7.05) -> (8, 6.15)
extrude "Label 4.1 digit 0 f" cut sketch "Label 4.1 digit 0 f sketch" along normal blind 1 bodies 10 in component "07 Spar fit coupon - 4.1 4.3 4.4 4.5 4.7"
ref_plane "WorkPlane3" through (0, 0, 9.4) normal (0, 0, 1) x (1, 0, 0) in component "07 Spar fit coupon - 4.1 4.3 4.4 4.5 4.7"
sketch "Label 4.1 digit 0 g sketch" plane through (0, 0, 9.4) normal (0, 0, 1) x (1, 0, 0) in component "07 Spar fit coupon - 4.1 4.3 4.4 4.5 4.7"
  line L0 (8, 5.85) -> (9.8, 5.85)
  line L1 (9.8, 5.85) -> (9.8, 6.15)
  line L2 (9.8, 6.15) -> (8, 6.15)
  line L3 (8, 6.15) -> (8, 5.85)
extrude "Label 4.1 digit 0 g" cut sketch "Label 4.1 digit 0 g sketch" along normal blind 1 bodies 10 in component "07 Spar fit coupon - 4.1 4.3 4.4 4.5 4.7"
ref_plane "WorkPlane4" through (0, 0, 9.4) normal (0, 0, 1) x (1, 0, 0) in component "07 Spar fit coupon - 4.1 4.3 4.4 4.5 4.7"
sketch "Label 4.1 digit 0 b sketch" plane through (0, 0, 9.4) normal (0, 0, 1) x (1, 0, 0) in component "07 Spar fit coupon - 4.1 4.3 4.4 4.5 4.7"
  line L0 (9.5, 6.15) -> (9.8, 6.15)
  line L1 (9.8, 6.15) -> (9.8, 7.05)
  line L2 (9.8, 7.05) -> (9.5, 7.05)
  line L3 (9.5, 7.05) -> (9.5, 6.15)
extrude "Label 4.1 digit 0 b" cut sketch "Label 4.1 digit 0 b sketch" along normal blind 1 bodies 10 in component "07 Spar fit coupon - 4.1 4.3 4.4 4.5 4.7"
ref_plane "WorkPlane5" through (0, 0, 9.4) normal (0, 0, 1) x (1, 0, 0) in component "07 Spar fit coupon - 4.1 4.3 4.4 4.5 4.7"
sketch "Label 4.1 digit 0 c sketch" plane through (0, 0, 9.4) normal (0, 0, 1) x (1, 0, 0) in component "07 Spar fit coupon - 4.1 4.3 4.4 4.5 4.7"
  line L0 (9.5, 4.95) -> (9.8, 4.95)
  line L1 (9.8, 4.95) -> (9.8, 5.85)
  line L2 (9.8, 5.85) -> (9.5, 5.85)
  line L3 (9.5, 5.85) -> (9.5, 4.95)
extrude "Label 4.1 digit 0 c" cut sketch "Label 4.1 digit 0 c sketch" along normal blind 1 bodies 10 in component "07 Spar fit coupon - 4.1 4.3 4.4 4.5 4.7"
ref_plane "WorkPlane6" through (0, 0, 9.4) normal (0, 0, 1) x (1, 0, 0) in component "07 Spar fit coupon - 4.1 4.3 4.4 4.5 4.7"
sketch "Label 4.1 dot sketch" plane through (0, 0, 9.4) normal (0, 0, 1) x (1, 0, 0) in component "07 Spar fit coupon - 4.1 4.3 4.4 4.5 4.7"
  line L0 (10.5, 4.5) -> (10.85, 4.5)
  line L1 (10.85, 4.5) -> (10.85, 4.85)
  line L2 (10.85, 4.85) -> (10.5, 4.85)
  line L3 (10.5, 4.85) -> (10.5, 4.5)
extrude "Label 4.1 dot" cut sketch "Label 4.1 dot sketch" along normal blind 1 bodies 10 in component "07 Spar fit coupon - 4.1 4.3 4.4 4.5 4.7"
ref_plane "WorkPlane7" through (0, 0, 9.4) normal (0, 0, 1) x (1, 0, 0) in component "07 Spar fit coupon - 4.1 4.3 4.4 4.5 4.7"
sketch "Label 4.1 digit 2 b sketch" plane through (0, 0, 9.4) normal (0, 0, 1) x (1, 0, 0) in component "07 Spar fit coupon - 4.1 4.3 4.4 4.5 4.7"
  line L0 (14.5, 6.15) -> (14.8, 6.15)
  line L1 (14.8, 6.15) -> (14.8, 7.05)
  line L2 (14.8, 7.05) -> (14.5, 7.05)
  line L3 (14.5, 7.05) -> (14.5, 6.15)
extrude "Label 4.1 digit 2 b" cut sketch "Label 4.1 digit 2 b sketch" along normal blind 1 bodies 10 in component "07 Spar fit coupon - 4.1 4.3 4.4 4.5 4.7"
ref_plane "WorkPlane8" through (0, 0, 9.4) normal (0, 0, 1) x (1, 0, 0) in component "07 Spar fit coupon - 4.1 4.3 4.4 4.5 4.7"
sketch "Label 4.1 digit 2 c sketch" plane through (0, 0, 9.4) normal (0, 0, 1) x (1, 0, 0) in component "07 Spar fit coupon - 4.1 4.3 4.4 4.5 4.7"
  line L0 (14.5, 4.95) -> (14.8, 4.95)
  line L1 (14.8, 4.95) -> (14.8, 5.85)
  line L2 (14.8, 5.85) -> (14.5, 5.85)
  line L3 (14.5, 5.85) -> (14.5, 4.95)
extrude "Label 4.1 digit 2 c" cut sketch "Label 4.1 digit 2 c sketch" along normal blind 1 bodies 10 in component "07 Spar fit coupon - 4.1 4.3 4.4 4.5 4.7"
ref_plane "WorkPlane9" through (-0.05, 0, 0) normal (1, 0, 0) x (0, 1, 0) in component "07 Spar fit coupon - 4.1 4.3 4.4 4.5 4.7"
sketch "Diamond 4.3 mm flat-width fit bore sketch" plane through (-0.05, 0, 0) normal (1, 0, 0) x (0, 0, -1) in component "07 Spar fit coupon - 4.1 4.3 4.4 4.5 4.7"
  line L0 (-4.5, 14.9594) -> (-1.4594, 18)
  line L1 (-1.4594, 18) -> (-4.5, 21.0406)
  line L2 (-4.5, 21.0406) -> (-7.5406, 18)
  line L3 (-7.5406, 18) -> (-4.5, 14.9594)
extrude "Diamond 4.3 mm flat-width fit bore" cut sketch "Diamond 4.3 mm flat-width fit bore sketch" along normal blind 24.1 bodies 10 in component "07 Spar fit coupon - 4.1 4.3 4.4 4.5 4.7"
ref_plane "WorkPlane10" through (0, 0, 9.4) normal (0, 0, 1) x (1, 0, 0) in component "07 Spar fit coupon - 4.1 4.3 4.4 4.5 4.7"
sketch "Label 4.3 digit 0 f sketch" plane through (0, 0, 9.4) normal (0, 0, 1) x (1, 0, 0) in component "07 Spar fit coupon - 4.1 4.3 4.4 4.5 4.7"
  line L0 (8, 18.15) -> (8.3, 18.15)
  line L1 (8.3, 18.15) -> (8.3, 19.05)
  line L2 (8.3, 19.05) -> (8, 19.05)
  line L3 (8, 19.05) -> (8, 18.15)
extrude "Label 4.3 digit 0 f" cut sketch "Label 4.3 digit 0 f sketch" along normal blind 1 bodies 10 in component "07 Spar fit coupon - 4.1 4.3 4.4 4.5 4.7"
ref_plane "WorkPlane11" through (0, 0, 9.4) normal (0, 0, 1) x (1, 0, 0) in component "07 Spar fit coupon - 4.1 4.3 4.4 4.5 4.7"
sketch "Label 4.3 digit 0 g sketch" plane through (0, 0, 9.4) normal (0, 0, 1) x (1, 0, 0) in component "07 Spar fit coupon - 4.1 4.3 4.4 4.5 4.7"
  line L0 (8, 17.85) -> (9.8, 17.85)
  line L1 (9.8, 17.85) -> (9.8, 18.15)
  line L2 (9.8, 18.15) -> (8, 18.15)
  line L3 (8, 18.15) -> (8, 17.85)
extrude "Label 4.3 digit 0 g" cut sketch "Label 4.3 digit 0 g sketch" along normal blind 1 bodies 10 in component "07 Spar fit coupon - 4.1 4.3 4.4 4.5 4.7"
ref_plane "WorkPlane12" through (0, 0, 9.4) normal (0, 0, 1) x (1, 0, 0) in component "07 Spar fit coupon - 4.1 4.3 4.4 4.5 4.7"
sketch "Label 4.3 digit 0 b sketch" plane through (0, 0, 9.4) normal (0, 0, 1) x (1, 0, 0) in component "07 Spar fit coupon - 4.1 4.3 4.4 4.5 4.7"
  line L0 (9.5, 18.15) -> (9.8, 18.15)
  line L1 (9.8, 18.15) -> (9.8, 19.05)
  line L2 (9.8, 19.05) -> (9.5, 19.05)
  line L3 (9.5, 19.05) -> (9.5, 18.15)
extrude "Label 4.3 digit 0 b" cut sketch "Label 4.3 digit 0 b sketch" along normal blind 1 bodies 10 in component "07 Spar fit coupon - 4.1 4.3 4.4 4.5 4.7"
ref_plane "WorkPlane13" through (0, 0, 9.4) normal (0, 0, 1) x (1, 0, 0) in component "07 Spar fit coupon - 4.1 4.3 4.4 4.5 4.7"
sketch "Label 4.3 digit 0 c sketch" plane through (0, 0, 9.4) normal (0, 0, 1) x (1, 0, 0) in component "07 Spar fit coupon - 4.1 4.3 4.4 4.5 4.7"
  line L0 (9.5, 16.95) -> (9.8, 16.95)
  line L1 (9.8, 16.95) -> (9.8, 17.85)
  line L2 (9.8, 17.85) -> (9.5, 17.85)
  line L3 (9.5, 17.85) -> (9.5, 16.95)
extrude "Label 4.3 digit 0 c" cut sketch "Label 4.3 digit 0 c sketch" along normal blind 1 bodies 10 in component "07 Spar fit coupon - 4.1 4.3 4.4 4.5 4.7"
ref_plane "WorkPlane14" through (0, 0, 9.4) normal (0, 0, 1) x (1, 0, 0) in component "07 Spar fit coupon - 4.1 4.3 4.4 4.5 4.7"
sketch "Label 4.3 dot sketch" plane through (0, 0, 9.4) normal (0, 0, 1) x (1, 0, 0) in component "07 Spar fit coupon - 4.1 4.3 4.4 4.5 4.7"
  line L0 (10.5, 16.5) -> (10.85, 16.5)
  line L1 (10.85, 16.5) -> (10.85, 16.85)
  line L2 (10.85, 16.85) -> (10.5, 16.85)
  line L3 (10.5, 16.85) -> (10.5, 16.5)
extrude "Label 4.3 dot" cut sketch "Label 4.3 dot sketch" along normal blind 1 bodies 10 in component "07 Spar fit coupon - 4.1 4.3 4.4 4.5 4.7"
ref_plane "WorkPlane15" through (0, 0, 9.4) normal (0, 0, 1) x (1, 0, 0) in component "07 Spar fit coupon - 4.1 4.3 4.4 4.5 4.7"
sketch "Label 4.3 digit 2 a sketch" plane through (0, 0, 9.4) normal (0, 0, 1) x (1, 0, 0) in component "07 Spar fit coupon - 4.1 4.3 4.4 4.5 4.7"
  line L0 (13, 19.2) -> (14.8, 19.2)
  line L1 (14.8, 19.2) -> (14.8, 19.5)
  line L2 (14.8, 19.5) -> (13, 19.5)
  line L3 (13, 19.5) -> (13, 19.2)
extrude "Label 4.3 digit 2 a" cut sketch "Label 4.3 digit 2 a sketch" along normal blind 1 bodies 10 in component "07 Spar fit coupon - 4.1 4.3 4.4 4.5 4.7"
ref_plane "WorkPlane16" through (0, 0, 9.4) normal (0, 0, 1) x (1, 0, 0) in component "07 Spar fit coupon - 4.1 4.3 4.4 4.5 4.7"
sketch "Label 4.3 digit 2 b sketch" plane through (0, 0, 9.4) normal (0, 0, 1) x (1, 0, 0) in component "07 Spar fit coupon - 4.1 4.3 4.4 4.5 4.7"
  line L0 (14.5, 18.15) -> (14.8, 18.15)
  line L1 (14.8, 18.15) -> (14.8, 19.05)
  line L2 (14.8, 19.05) -> (14.5, 19.05)
  line L3 (14.5, 19.05) -> (14.5, 18.15)
extrude "Label 4.3 digit 2 b" cut sketch "Label 4.3 digit 2 b sketch" along normal blind 1 bodies 10 in component "07 Spar fit coupon - 4.1 4.3 4.4 4.5 4.7"
ref_plane "WorkPlane17" through (0, 0, 9.4) normal (0, 0, 1) x (1, 0, 0) in component "07 Spar fit coupon - 4.1 4.3 4.4 4.5 4.7"
sketch "Label 4.3 digit 2 g sketch" plane through (0, 0, 9.4) normal (0, 0, 1) x (1, 0, 0) in component "07 Spar fit coupon - 4.1 4.3 4.4 4.5 4.7"
  line L0 (13, 17.85) -> (14.8, 17.85)
  line L1 (14.8, 17.85) -> (14.8, 18.15)
  line L2 (14.8, 18.15) -> (13, 18.15)
  line L3 (13, 18.15) -> (13, 17.85)
extrude "Label 4.3 digit 2 g" cut sketch "Label 4.3 digit 2 g sketch" along normal blind 1 bodies 10 in component "07 Spar fit coupon - 4.1 4.3 4.4 4.5 4.7"
ref_plane "WorkPlane18" through (0, 0, 9.4) normal (0, 0, 1) x (1, 0, 0) in component "07 Spar fit coupon - 4.1 4.3 4.4 4.5 4.7"
sketch "Label 4.3 digit 2 c sketch" plane through (0, 0, 9.4) normal (0, 0, 1) x (1, 0, 0) in component "07 Spar fit coupon - 4.1 4.3 4.4 4.5 4.7"
  line L0 (14.5, 16.95) -> (14.8, 16.95)
  line L1 (14.8, 16.95) -> (14.8, 17.85)
  line L2 (14.8, 17.85) -> (14.5, 17.85)
  line L3 (14.5, 17.85) -> (14.5, 16.95)
extrude "Label 4.3 digit 2 c" cut sketch "Label 4.3 digit 2 c sketch" along normal blind 1 bodies 10 in component "07 Spar fit coupon - 4.1 4.3 4.4 4.5 4.7"
ref_plane "WorkPlane19" through (0, 0, 9.4) normal (0, 0, 1) x (1, 0, 0) in component "07 Spar fit coupon - 4.1 4.3 4.4 4.5 4.7"
sketch "Label 4.3 digit 2 d sketch" plane through (0, 0, 9.4) normal (0, 0, 1) x (1, 0, 0) in component "07 Spar fit coupon - 4.1 4.3 4.4 4.5 4.7"
  line L0 (13, 16.5) -> (14.8, 16.5)
  line L1 (14.8, 16.5) -> (14.8, 16.8)
  line L2 (14.8, 16.8) -> (13, 16.8)
  line L3 (13, 16.8) -> (13, 16.5)
extrude "Label 4.3 digit 2 d" cut sketch "Label 4.3 digit 2 d sketch" along normal blind 1 bodies 10 in component "07 Spar fit coupon - 4.1 4.3 4.4 4.5 4.7"
ref_plane "WorkPlane20" through (-0.05, 0, 0) normal (1, 0, 0) x (0, 1, 0) in component "07 Spar fit coupon - 4.1 4.3 4.4 4.5 4.7"
sketch "Diamond 4.4 mm flat-width fit bore sketch" plane through (-0.05, 0, 0) normal (1, 0, 0) x (0, 0, -1) in component "07 Spar fit coupon - 4.1 4.3 4.4 4.5 4.7"
  line L0 (-4.5, 26.8887) -> (-1.3887, 30)
  line L1 (-1.3887, 30) -> (-4.5, 33.1113)
  line L2 (-4.5, 33.1113) -> (-7.6113, 30)
  line L3 (-7.6113, 30) -> (-4.5, 26.8887)
extrude "Diamond 4.4 mm flat-width fit bore" cut sketch "Diamond 4.4 mm flat-width fit bore sketch" along normal blind 24.1 bodies 10 in component "07 Spar fit coupon - 4.1 4.3 4.4 4.5 4.7"
ref_plane "WorkPlane21" through (0, 0, 9.4) normal (0, 0, 1) x (1, 0, 0) in component "07 Spar fit coupon - 4.1 4.3 4.4 4.5 4.7"
sketch "Label 4.4 digit 0 f sketch" plane through (0, 0, 9.4) normal (0, 0, 1) x (1, 0, 0) in component "07 Spar fit coupon - 4.1 4.3 4.4 4.5 4.7"
  line L0 (8, 30.15) -> (8.3, 30.15)
  line L1 (8.3, 30.15) -> (8.3, 31.05)
  line L2 (8.3, 31.05) -> (8, 31.05)
  line L3 (8, 31.05) -> (8, 30.15)
extrude "Label 4.4 digit 0 f" cut sketch "Label 4.4 digit 0 f sketch" along normal blind 1 bodies 10 in component "07 Spar fit coupon - 4.1 4.3 4.4 4.5 4.7"
ref_plane "WorkPlane22" through (0, 0, 9.4) normal (0, 0, 1) x (1, 0, 0) in component "07 Spar fit coupon - 4.1 4.3 4.4 4.5 4.7"
sketch "Label 4.4 digit 0 g sketch" plane through (0, 0, 9.4) normal (0, 0, 1) x (1, 0, 0) in component "07 Spar fit coupon - 4.1 4.3 4.4 4.5 4.7"
  line L0 (8, 29.85) -> (9.8, 29.85)
  line L1 (9.8, 29.85) -> (9.8, 30.15)
  line L2 (9.8, 30.15) -> (8, 30.15)
  line L3 (8, 30.15) -> (8, 29.85)
extrude "Label 4.4 digit 0 g" cut sketch "Label 4.4 digit 0 g sketch" along normal blind 1 bodies 10 in component "07 Spar fit coupon - 4.1 4.3 4.4 4.5 4.7"
ref_plane "WorkPlane23" through (0, 0, 9.4) normal (0, 0, 1) x (1, 0, 0) in component "07 Spar fit coupon - 4.1 4.3 4.4 4.5 4.7"
sketch "Label 4.4 digit 0 b sketch" plane through (0, 0, 9.4) normal (0, 0, 1) x (1, 0, 0) in component "07 Spar fit coupon - 4.1 4.3 4.4 4.5 4.7"
  line L0 (9.5, 30.15) -> (9.8, 30.15)
  line L1 (9.8, 30.15) -> (9.8, 31.05)
  line L2 (9.8, 31.05) -> (9.5, 31.05)
  line L3 (9.5, 31.05) -> (9.5, 30.15)
extrude "Label 4.4 digit 0 b" cut sketch "Label 4.4 digit 0 b sketch" along normal blind 1 bodies 10 in component "07 Spar fit coupon - 4.1 4.3 4.4 4.5 4.7"
ref_plane "WorkPlane24" through (0, 0, 9.4) normal (0, 0, 1) x (1, 0, 0) in component "07 Spar fit coupon - 4.1 4.3 4.4 4.5 4.7"
sketch "Label 4.4 digit 0 c sketch" plane through (0, 0, 9.4) normal (0, 0, 1) x (1, 0, 0) in component "07 Spar fit coupon - 4.1 4.3 4.4 4.5 4.7"
  line L0 (9.5, 28.95) -> (9.8, 28.95)
  line L1 (9.8, 28.95) -> (9.8, 29.85)
  line L2 (9.8, 29.85) -> (9.5, 29.85)
  line L3 (9.5, 29.85) -> (9.5, 28.95)
extrude "Label 4.4 digit 0 c" cut sketch "Label 4.4 digit 0 c sketch" along normal blind 1 bodies 10 in component "07 Spar fit coupon - 4.1 4.3 4.4 4.5 4.7"
ref_plane "WorkPlane25" through (0, 0, 9.4) normal (0, 0, 1) x (1, 0, 0) in component "07 Spar fit coupon - 4.1 4.3 4.4 4.5 4.7"
sketch "Label 4.4 dot sketch" plane through (0, 0, 9.4) normal (0, 0, 1) x (1, 0, 0) in component "07 Spar fit coupon - 4.1 4.3 4.4 4.5 4.7"
  line L0 (10.5, 28.5) -> (10.85, 28.5)
  line L1 (10.85, 28.5) -> (10.85, 28.85)
  line L2 (10.85, 28.85) -> (10.5, 28.85)
  line L3 (10.5, 28.85) -> (10.5, 28.5)
extrude "Label 4.4 dot" cut sketch "Label 4.4 dot sketch" along normal blind 1 bodies 10 in component "07 Spar fit coupon - 4.1 4.3 4.4 4.5 4.7"
ref_plane "WorkPlane26" through (0, 0, 9.4) normal (0, 0, 1) x (1, 0, 0) in component "07 Spar fit coupon - 4.1 4.3 4.4 4.5 4.7"
sketch "Label 4.4 digit 2 f sketch" plane through (0, 0, 9.4) normal (0, 0, 1) x (1, 0, 0) in component "07 Spar fit coupon - 4.1 4.3 4.4 4.5 4.7"
  line L0 (13, 30.15) -> (13.3, 30.15)
  line L1 (13.3, 30.15) -> (13.3, 31.05)
  line L2 (13.3, 31.05) -> (13, 31.05)
  line L3 (13, 31.05) -> (13, 30.15)
extrude "Label 4.4 digit 2 f" cut sketch "Label 4.4 digit 2 f sketch" along normal blind 1 bodies 10 in component "07 Spar fit coupon - 4.1 4.3 4.4 4.5 4.7"
ref_plane "WorkPlane27" through (0, 0, 9.4) normal (0, 0, 1) x (1, 0, 0) in component "07 Spar fit coupon - 4.1 4.3 4.4 4.5 4.7"
sketch "Label 4.4 digit 2 g sketch" plane through (0, 0, 9.4) normal (0, 0, 1) x (1, 0, 0) in component "07 Spar fit coupon - 4.1 4.3 4.4 4.5 4.7"
  line L0 (13, 29.85) -> (14.8, 29.85)
  line L1 (14.8, 29.85) -> (14.8, 30.15)
  line L2 (14.8, 30.15) -> (13, 30.15)
  line L3 (13, 30.15) -> (13, 29.85)
extrude "Label 4.4 digit 2 g" cut sketch "Label 4.4 digit 2 g sketch" along normal blind 1 bodies 10 in component "07 Spar fit coupon - 4.1 4.3 4.4 4.5 4.7"
ref_plane "WorkPlane28" through (0, 0, 9.4) normal (0, 0, 1) x (1, 0, 0) in component "07 Spar fit coupon - 4.1 4.3 4.4 4.5 4.7"
sketch "Label 4.4 digit 2 b sketch" plane through (0, 0, 9.4) normal (0, 0, 1) x (1, 0, 0) in component "07 Spar fit coupon - 4.1 4.3 4.4 4.5 4.7"
  line L0 (14.5, 30.15) -> (14.8, 30.15)
  line L1 (14.8, 30.15) -> (14.8, 31.05)
  line L2 (14.8, 31.05) -> (14.5, 31.05)
  line L3 (14.5, 31.05) -> (14.5, 30.15)
extrude "Label 4.4 digit 2 b" cut sketch "Label 4.4 digit 2 b sketch" along normal blind 1 bodies 10 in component "07 Spar fit coupon - 4.1 4.3 4.4 4.5 4.7"
ref_plane "WorkPlane29" through (0, 0, 9.4) normal (0, 0, 1) x (1, 0, 0) in component "07 Spar fit coupon - 4.1 4.3 4.4 4.5 4.7"
sketch "Label 4.4 digit 2 c sketch" plane through (0, 0, 9.4) normal (0, 0, 1) x (1, 0, 0) in component "07 Spar fit coupon - 4.1 4.3 4.4 4.5 4.7"
  line L0 (14.5, 28.95) -> (14.8, 28.95)
  line L1 (14.8, 28.95) -> (14.8, 29.85)
  line L2 (14.8, 29.85) -> (14.5, 29.85)
  line L3 (14.5, 29.85) -> (14.5, 28.95)
extrude "Label 4.4 digit 2 c" cut sketch "Label 4.4 digit 2 c sketch" along normal blind 1 bodies 10 in component "07 Spar fit coupon - 4.1 4.3 4.4 4.5 4.7"
ref_plane "WorkPlane30" through (-0.05, 0, 0) normal (1, 0, 0) x (0, 1, 0) in component "07 Spar fit coupon - 4.1 4.3 4.4 4.5 4.7"
sketch "Diamond 4.5 mm flat-width fit bore sketch" plane through (-0.05, 0, 0) normal (1, 0, 0) x (0, 0, -1) in component "07 Spar fit coupon - 4.1 4.3 4.4 4.5 4.7"
  line L0 (-4.5, 38.818) -> (-1.318, 42)
  line L1 (-1.318, 42) -> (-4.5, 45.182)
  line L2 (-4.5, 45.182) -> (-7.682, 42)
  line L3 (-7.682, 42) -> (-4.5, 38.818)
extrude "Diamond 4.5 mm flat-width fit bore" cut sketch "Diamond 4.5 mm flat-width fit bore sketch" along normal blind 24.1 bodies 10 in component "07 Spar fit coupon - 4.1 4.3 4.4 4.5 4.7"
ref_plane "WorkPlane31" through (0, 0, 9.4) normal (0, 0, 1) x (1, 0, 0) in component "07 Spar fit coupon - 4.1 4.3 4.4 4.5 4.7"
sketch "Label 4.5 digit 0 f sketch" plane through (0, 0, 9.4) normal (0, 0, 1) x (1, 0, 0) in component "07 Spar fit coupon - 4.1 4.3 4.4 4.5 4.7"
  line L0 (8, 42.15) -> (8.3, 42.15)
  line L1 (8.3, 42.15) -> (8.3, 43.05)
  line L2 (8.3, 43.05) -> (8, 43.05)
  line L3 (8, 43.05) -> (8, 42.15)
extrude "Label 4.5 digit 0 f" cut sketch "Label 4.5 digit 0 f sketch" along normal blind 1 bodies 10 in component "07 Spar fit coupon - 4.1 4.3 4.4 4.5 4.7"
ref_plane "WorkPlane32" through (0, 0, 9.4) normal (0, 0, 1) x (1, 0, 0) in component "07 Spar fit coupon - 4.1 4.3 4.4 4.5 4.7"
sketch "Label 4.5 digit 0 g sketch" plane through (0, 0, 9.4) normal (0, 0, 1) x (1, 0, 0) in component "07 Spar fit coupon - 4.1 4.3 4.4 4.5 4.7"
  line L0 (8, 41.85) -> (9.8, 41.85)
  line L1 (9.8, 41.85) -> (9.8, 42.15)
  line L2 (9.8, 42.15) -> (8, 42.15)
  line L3 (8, 42.15) -> (8, 41.85)
extrude "Label 4.5 digit 0 g" cut sketch "Label 4.5 digit 0 g sketch" along normal blind 1 bodies 10 in component "07 Spar fit coupon - 4.1 4.3 4.4 4.5 4.7"
ref_plane "WorkPlane33" through (0, 0, 9.4) normal (0, 0, 1) x (1, 0, 0) in component "07 Spar fit coupon - 4.1 4.3 4.4 4.5 4.7"
sketch "Label 4.5 digit 0 b sketch" plane through (0, 0, 9.4) normal (0, 0, 1) x (1, 0, 0) in component "07 Spar fit coupon - 4.1 4.3 4.4 4.5 4.7"
  line L0 (9.5, 42.15) -> (9.8, 42.15)
  line L1 (9.8, 42.15) -> (9.8, 43.05)
  line L2 (9.8, 43.05) -> (9.5, 43.05)
  line L3 (9.5, 43.05) -> (9.5, 42.15)
extrude "Label 4.5 digit 0 b" cut sketch "Label 4.5 digit 0 b sketch" along normal blind 1 bodies 10 in component "07 Spar fit coupon - 4.1 4.3 4.4 4.5 4.7"
ref_plane "WorkPlane34" through (0, 0, 9.4) normal (0, 0, 1) x (1, 0, 0) in component "07 Spar fit coupon - 4.1 4.3 4.4 4.5 4.7"
sketch "Label 4.5 digit 0 c sketch" plane through (0, 0, 9.4) normal (0, 0, 1) x (1, 0, 0) in component "07 Spar fit coupon - 4.1 4.3 4.4 4.5 4.7"
  line L0 (9.5, 40.95) -> (9.8, 40.95)
  line L1 (9.8, 40.95) -> (9.8, 41.85)
  line L2 (9.8, 41.85) -> (9.5, 41.85)
  line L3 (9.5, 41.85) -> (9.5, 40.95)
extrude "Label 4.5 digit 0 c" cut sketch "Label 4.5 digit 0 c sketch" along normal blind 1 bodies 10 in component "07 Spar fit coupon - 4.1 4.3 4.4 4.5 4.7"
ref_plane "WorkPlane35" through (0, 0, 9.4) normal (0, 0, 1) x (1, 0, 0) in component "07 Spar fit coupon - 4.1 4.3 4.4 4.5 4.7"
sketch "Label 4.5 dot sketch" plane through (0, 0, 9.4) normal (0, 0, 1) x (1, 0, 0) in component "07 Spar fit coupon - 4.1 4.3 4.4 4.5 4.7"
  line L0 (10.5, 40.5) -> (10.85, 40.5)
  line L1 (10.85, 40.5) -> (10.85, 40.85)
  line L2 (10.85, 40.85) -> (10.5, 40.85)
  line L3 (10.5, 40.85) -> (10.5, 40.5)